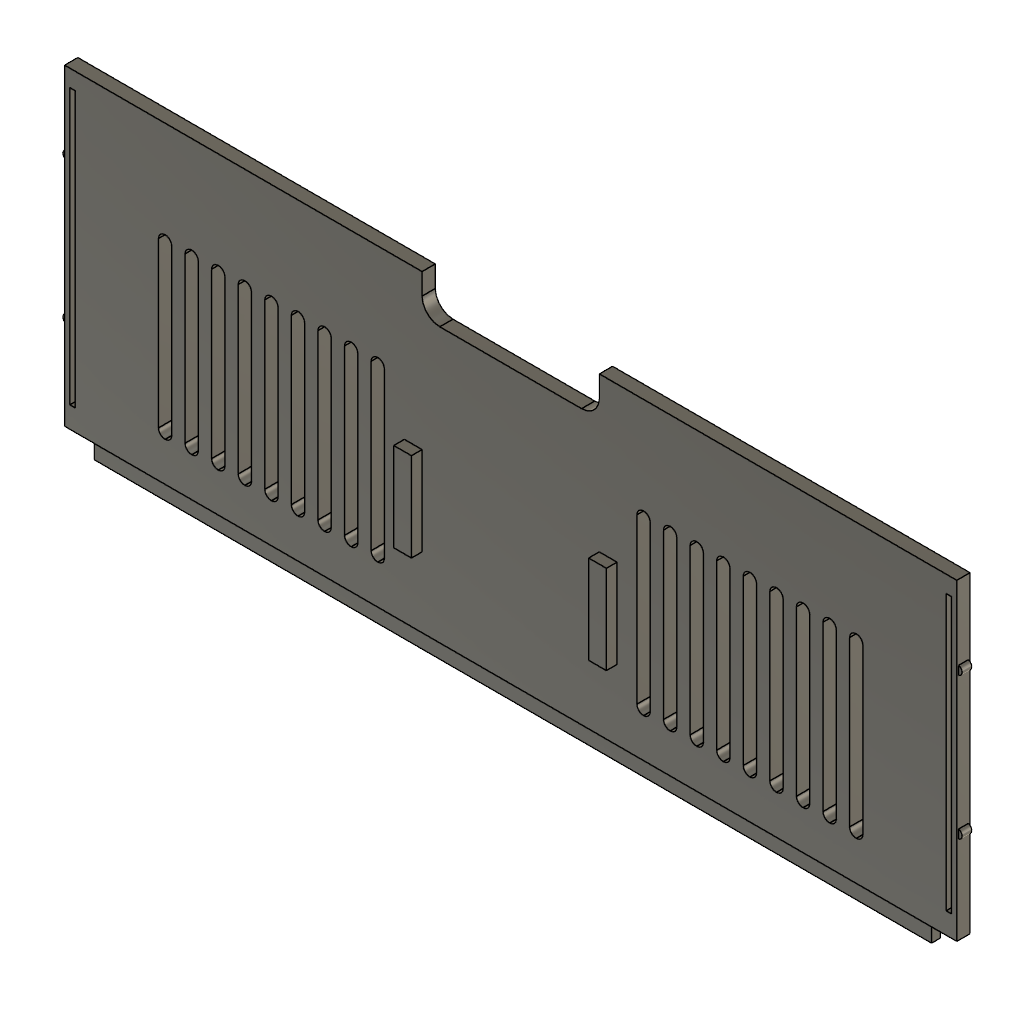
Back_Door (Autodesk Fusion 360 design; units mm, degrees)
part number: 2026-10-19-10-28-41-886
Autodesk Fusion 360 part; units mm, degrees
sketch "door_plate" plane through (0, 0, 0) normal (0, 0, 1) x (1, 0, 0)
  line L0 (-100.7, 229) -> (100.7, 229)
  line L1 (100.7, 229) -> (100.7, 232)
  line L2 (100.7, 232) -> (-100.7, 232)
  line L3 (-100.7, 232) -> (-100.7, 229)
extrude "door_plate (1)" add sketch "door_plate" along normal blind 70.6 from surface at 9.2
sketch "door_tongue" plane through (0, 0, 0) normal (0, 0, 1) x (1, 0, 0)
  line L0 (-94.5, 229.5) -> (94.5, 229.5)
  line L1 (94.5, 229.5) -> (94.5, 231.5)
  line L2 (94.5, 231.5) -> (-94.5, 231.5)
  line L3 (-94.5, 231.5) -> (-94.5, 229.5)
extrude "door_tongue (1)" add sketch "door_tongue" along normal blind 3.8 from surface at 5.5
sketch "door_flex_slot" plane through (0, 0, 0) normal (0, 0, 1) x (1, 0, 0)
  line L0 (98.3, 228.5) -> (99.5, 228.5)
  line L1 (99.5, 228.5) -> (99.5, 232.5)
  line L2 (99.5, 232.5) -> (98.3, 232.5)
  line L3 (98.3, 232.5) -> (98.3, 228.5)
extrude "door_flex_slot (1)" cut sketch "door_flex_slot" along normal blind 62 from surface at 14
sketch "door_bump" plane through (0, 0, 0) normal (0, 1, 0) x (1, 0, 0)
  circle A0 centre (100.5, -30) radius 1
  circle A1 centre (100.5, -62) radius 1
extrude "door_bump (1)" add sketch "door_bump" along normal blind 2.2 from surface at 229.4
sketch "door_bumper" plane through (0, 0, 0) normal (0, 0, 1) x (1, 0, 0)
  line L0 (20, 226.6) -> (24, 226.6)
  line L1 (24, 226.6) -> (24, 229.01)
  line L2 (24, 229.01) -> (20, 229.01)
  line L3 (20, 229.01) -> (20, 226.6)
extrude "door_bumper (1)" add sketch "door_bumper" along normal blind 20 from surface at 25
sketch "door_flex_slot (1)" plane through (0, 0, 0) normal (0, 0, 1) x (1, 0, 0)
  line L0 (-99.5, 228.5) -> (-98.3, 228.5)
  line L1 (-98.3, 228.5) -> (-98.3, 232.5)
  line L2 (-98.3, 232.5) -> (-99.5, 232.5)
  line L3 (-99.5, 232.5) -> (-99.5, 228.5)
extrude "door_flex_slot (2)" cut sketch "door_flex_slot (1)" along normal blind 62 from surface at 14
sketch "door_bump (1)" plane through (0, 0, 0) normal (0, 1, 0) x (1, 0, 0)
  circle A0 centre (-100.5, -30) radius 1
  circle A1 centre (-100.5, -62) radius 1
extrude "door_bump (2)" add sketch "door_bump (1)" along normal blind 2.2 from surface at 229.4
sketch "door_bumper (1)" plane through (0, 0, 0) normal (0, 0, 1) x (1, 0, 0)
  line L0 (-24, 226.6) -> (-20, 226.6)
  line L1 (-20, 226.6) -> (-20, 229.01)
  line L2 (-20, 229.01) -> (-24, 229.01)
  line L3 (-24, 229.01) -> (-24, 226.6)
extrude "door_bumper (2)" add sketch "door_bumper (1)" along normal blind 20 from surface at 25
sketch "door_finger_notch" plane through (0, 0, 0) normal (0, 1, 0) x (1, 0, 0)
  line L0 (-16, -71) -> (16, -71)
  arc A0 (20, -75) -> (16, -71) centre (16, -75) ccw
  line L1 (20, -75) -> (20, -81)
  arc A1 (16, -85) -> (20, -81) centre (16, -81) ccw
  line L2 (16, -85) -> (-16, -85)
  arc A2 (-20, -81) -> (-16, -85) centre (-16, -81) ccw
  line L3 (-20, -81) -> (-20, -75)
  arc A3 (-16, -71) -> (-20, -75) centre (-16, -75) ccw
extrude "door_finger_notch (1)" cut sketch "door_finger_notch" along normal blind 4 from surface at 228.5
sketch "door_vents" plane through (0, 0, 0) normal (0, 1, 0) x (1, 0, 0)
  line L0 (29.99, -18) -> (30.01, -18)
  arc A0 (31.5, -19.49) -> (30.01, -18) centre (30.01, -19.49) ccw
  line L1 (31.5, -19.49) -> (31.5, -56.51)
  arc A1 (30.01, -58) -> (31.5, -56.51) centre (30.01, -56.51) ccw
  line L2 (30.01, -58) -> (29.99, -58)
  arc A2 (28.5, -56.51) -> (29.99, -58) centre (29.99, -56.51) ccw
  line L3 (28.5, -56.51) -> (28.5, -19.49)
  arc A3 (29.99, -18) -> (28.5, -19.49) centre (29.99, -19.49) ccw
  line L4 (-30.01, -18) -> (-29.99, -18)
  arc A4 (-28.5, -19.49) -> (-29.99, -18) centre (-29.99, -19.49) ccw
  line L5 (-28.5, -19.49) -> (-28.5, -56.51)
  arc A5 (-29.99, -58) -> (-28.5, -56.51) centre (-29.99, -56.51) ccw
  line L6 (-29.99, -58) -> (-30.01, -58)
  arc A6 (-31.5, -56.51) -> (-30.01, -58) centre (-30.01, -56.51) ccw
  line L7 (-31.5, -56.51) -> (-31.5, -19.49)
  arc A7 (-30.01, -18) -> (-31.5, -19.49) centre (-30.01, -19.49) ccw
  line L8 (35.99, -18) -> (36.01, -18)
  arc A8 (37.5, -19.49) -> (36.01, -18) centre (36.01, -19.49) ccw
  line L9 (37.5, -19.49) -> (37.5, -56.51)
  arc A9 (36.01, -58) -> (37.5, -56.51) centre (36.01, -56.51) ccw
  line L10 (36.01, -58) -> (35.99, -58)
  arc A10 (34.5, -56.51) -> (35.99, -58) centre (35.99, -56.51) ccw
  line L11 (34.5, -56.51) -> (34.5, -19.49)
  arc A11 (35.99, -18) -> (34.5, -19.49) centre (35.99, -19.49) ccw
  line L12 (-36.01, -18) -> (-35.99, -18)
  arc A12 (-34.5, -19.49) -> (-35.99, -18) centre (-35.99, -19.49) ccw
  line L13 (-34.5, -19.49) -> (-34.5, -56.51)
  arc A13 (-35.99, -58) -> (-34.5, -56.51) centre (-35.99, -56.51) ccw
  line L14 (-35.99, -58) -> (-36.01, -58)
  arc A14 (-37.5, -56.51) -> (-36.01, -58) centre (-36.01, -56.51) ccw
  line L15 (-37.5, -56.51) -> (-37.5, -19.49)
  arc A15 (-36.01, -18) -> (-37.5, -19.49) centre (-36.01, -19.49) ccw
  line L16 (41.99, -18) -> (42.01, -18)
  arc A16 (43.5, -19.49) -> (42.01, -18) centre (42.01, -19.49) ccw
  line L17 (43.5, -19.49) -> (43.5, -56.51)
  arc A17 (42.01, -58) -> (43.5, -56.51) centre (42.01, -56.51) ccw
  line L18 (42.01, -58) -> (41.99, -58)
  arc A18 (40.5, -56.51) -> (41.99, -58) centre (41.99, -56.51) ccw
  line L19 (40.5, -56.51) -> (40.5, -19.49)
  arc A19 (41.99, -18) -> (40.5, -19.49) centre (41.99, -19.49) ccw
  line L20 (-42.01, -18) -> (-41.99, -18)
  arc A20 (-40.5, -19.49) -> (-41.99, -18) centre (-41.99, -19.49) ccw
  line L21 (-40.5, -19.49) -> (-40.5, -56.51)
  arc A21 (-41.99, -58) -> (-40.5, -56.51) centre (-41.99, -56.51) ccw
  line L22 (-41.99, -58) -> (-42.01, -58)
  arc A22 (-43.5, -56.51) -> (-42.01, -58) centre (-42.01, -56.51) ccw
  line L23 (-43.5, -56.51) -> (-43.5, -19.49)
  arc A23 (-42.01, -18) -> (-43.5, -19.49) centre (-42.01, -19.49) ccw
  line L24 (47.99, -18) -> (48.01, -18)
  arc A24 (49.5, -19.49) -> (48.01, -18) centre (48.01, -19.49) ccw
  line L25 (49.5, -19.49) -> (49.5, -56.51)
  arc A25 (48.01, -58) -> (49.5, -56.51) centre (48.01, -56.51) ccw
  line L26 (48.01, -58) -> (47.99, -58)
  arc A26 (46.5, -56.51) -> (47.99, -58) centre (47.99, -56.51) ccw
  line L27 (46.5, -56.51) -> (46.5, -19.49)
  arc A27 (47.99, -18) -> (46.5, -19.49) centre (47.99, -19.49) ccw
  line L28 (-48.01, -18) -> (-47.99, -18)
  arc A28 (-46.5, -19.49) -> (-47.99, -18) centre (-47.99, -19.49) ccw
  line L29 (-46.5, -19.49) -> (-46.5, -56.51)
  arc A29 (-47.99, -58) -> (-46.5, -56.51) centre (-47.99, -56.51) ccw
  line L30 (-47.99, -58) -> (-48.01, -58)
  arc A30 (-49.5, -56.51) -> (-48.01, -58) centre (-48.01, -56.51) ccw
  line L31 (-49.5, -56.51) -> (-49.5, -19.49)
  arc A31 (-48.01, -18) -> (-49.5, -19.49) centre (-48.01, -19.49) ccw
  line L32 (53.99, -18) -> (54.01, -18)
  arc A32 (55.5, -19.49) -> (54.01, -18) centre (54.01, -19.49) ccw
  line L33 (55.5, -19.49) -> (55.5, -56.51)
  arc A33 (54.01, -58) -> (55.5, -56.51) centre (54.01, -56.51) ccw
  line L34 (54.01, -58) -> (53.99, -58)
  arc A34 (52.5, -56.51) -> (53.99, -58) centre (53.99, -56.51) ccw
  line L35 (52.5, -56.51) -> (52.5, -19.49)
  arc A35 (53.99, -18) -> (52.5, -19.49) centre (53.99, -19.49) ccw
  line L36 (-54.01, -18) -> (-53.99, -18)
  arc A36 (-52.5, -19.49) -> (-53.99, -18) centre (-53.99, -19.49) ccw
  line L37 (-52.5, -19.49) -> (-52.5, -56.51)
  arc A37 (-53.99, -58) -> (-52.5, -56.51) centre (-53.99, -56.51) ccw
  line L38 (-53.99, -58) -> (-54.01, -58)
  arc A38 (-55.5, -56.51) -> (-54.01, -58) centre (-54.01, -56.51) ccw
  line L39 (-55.5, -56.51) -> (-55.5, -19.49)
  arc A39 (-54.01, -18) -> (-55.5, -19.49) centre (-54.01, -19.49) ccw
  line L40 (59.99, -18) -> (60.01, -18)
  arc A40 (61.5, -19.49) -> (60.01, -18) centre (60.01, -19.49) ccw
  line L41 (61.5, -19.49) -> (61.5, -56.51)
  arc A41 (60.01, -58) -> (61.5, -56.51) centre (60.01, -56.51) ccw
  line L42 (60.01, -58) -> (59.99, -58)
  arc A42 (58.5, -56.51) -> (59.99, -58) centre (59.99, -56.51) ccw
  line L43 (58.5, -56.51) -> (58.5, -19.49)
  arc A43 (59.99, -18) -> (58.5, -19.49) centre (59.99, -19.49) ccw
  line L44 (-60.01, -18) -> (-59.99, -18)
  arc A44 (-58.5, -19.49) -> (-59.99, -18) centre (-59.99, -19.49) ccw
  line L45 (-58.5, -19.49) -> (-58.5, -56.51)
  arc A45 (-59.99, -58) -> (-58.5, -56.51) centre (-59.99, -56.51) ccw
  line L46 (-59.99, -58) -> (-60.01, -58)
  arc A46 (-61.5, -56.51) -> (-60.01, -58) centre (-60.01, -56.51) ccw
  line L47 (-61.5, -56.51) -> (-61.5, -19.49)
  arc A47 (-60.01, -18) -> (-61.5, -19.49) centre (-60.01, -19.49) ccw
  line L48 (65.99, -18) -> (66.01, -18)
  arc A48 (67.5, -19.49) -> (66.01, -18) centre (66.01, -19.49) ccw
  line L49 (67.5, -19.49) -> (67.5, -56.51)
  arc A49 (66.01, -58) -> (67.5, -56.51) centre (66.01, -56.51) ccw
  line L50 (66.01, -58) -> (65.99, -58)
  arc A50 (64.5, -56.51) -> (65.99, -58) centre (65.99, -56.51) ccw
  line L51 (64.5, -56.51) -> (64.5, -19.49)
  arc A51 (65.99, -18) -> (64.5, -19.49) centre (65.99, -19.49) ccw
  line L52 (-66.01, -18) -> (-65.99, -18)
  arc A52 (-64.5, -19.49) -> (-65.99, -18) centre (-65.99, -19.49) ccw
  line L53 (-64.5, -19.49) -> (-64.5, -56.51)
  arc A53 (-65.99, -58) -> (-64.5, -56.51) centre (-65.99, -56.51) ccw
  line L54 (-65.99, -58) -> (-66.01, -58)
  arc A54 (-67.5, -56.51) -> (-66.01, -58) centre (-66.01, -56.51) ccw
  line L55 (-67.5, -56.51) -> (-67.5, -19.49)
  arc A55 (-66.01, -18) -> (-67.5, -19.49) centre (-66.01, -19.49) ccw
  line L56 (71.99, -18) -> (72.01, -18)
  arc A56 (73.5, -19.49) -> (72.01, -18) centre (72.01, -19.49) ccw
  line L57 (73.5, -19.49) -> (73.5, -56.51)
  arc A57 (72.01, -58) -> (73.5, -56.51) centre (72.01, -56.51) ccw
  line L58 (72.01, -58) -> (71.99, -58)
  arc A58 (70.5, -56.51) -> (71.99, -58) centre (71.99, -56.51) ccw
  line L59 (70.5, -56.51) -> (70.5, -19.49)
  arc A59 (71.99, -18) -> (70.5, -19.49) centre (71.99, -19.49) ccw
  line L60 (-72.01, -18) -> (-71.99, -18)
  arc A60 (-70.5, -19.49) -> (-71.99, -18) centre (-71.99, -19.49) ccw
  line L61 (-70.5, -19.49) -> (-70.5, -56.51)
  arc A61 (-71.99, -58) -> (-70.5, -56.51) centre (-71.99, -56.51) ccw
  line L62 (-71.99, -58) -> (-72.01, -58)
  arc A62 (-73.5, -56.51) -> (-72.01, -58) centre (-72.01, -56.51) ccw
  line L63 (-73.5, -56.51) -> (-73.5, -19.49)
  arc A63 (-72.01, -18) -> (-73.5, -19.49) centre (-72.01, -19.49) ccw
  line L64 (77.99, -18) -> (78.01, -18)
  arc A64 (79.5, -19.49) -> (78.01, -18) centre (78.01, -19.49) ccw
  line L65 (79.5, -19.49) -> (79.5, -56.51)
  arc A65 (78.01, -58) -> (79.5, -56.51) centre (78.01, -56.51) ccw
  line L66 (78.01, -58) -> (77.99, -58)
  arc A66 (76.5, -56.51) -> (77.99, -58) centre (77.99, -56.51) ccw
  line L67 (76.5, -56.51) -> (76.5, -19.49)
  arc A67 (77.99, -18) -> (76.5, -19.49) centre (77.99, -19.49) ccw
  line L68 (-78.01, -18) -> (-77.99, -18)
  arc A68 (-76.5, -19.49) -> (-77.99, -18) centre (-77.99, -19.49) ccw
  line L69 (-76.5, -19.49) -> (-76.5, -56.51)
  arc A69 (-77.99, -58) -> (-76.5, -56.51) centre (-77.99, -56.51) ccw
  line L70 (-77.99, -58) -> (-78.01, -58)
  arc A70 (-79.5, -56.51) -> (-78.01, -58) centre (-78.01, -56.51) ccw
  line L71 (-79.5, -56.51) -> (-79.5, -19.49)
  arc A71 (-78.01, -18) -> (-79.5, -19.49) centre (-78.01, -19.49) ccw
extrude "door_vents (1)" cut sketch "door_vents" along normal blind 4 from surface at 228.5
sketch "surge_mark" plane through (0, 0, 0) normal (0, 1, 0) x (1, 0, 0)
  circle A0 centre (0, -40) radius 18
  line L0 (5.2051, -38.7127) -> (-1.107, -54.8795)
  line L1 (-1.107, -54.8795) -> (-5.9778, -46.5759)
  line L2 (-5.9778, -46.5759) -> (0.1503, -42.2742)
  line L3 (0.1503, -42.2742) -> (-2.9177, -38.4458)
  line L4 (-2.9177, -38.4458) -> (-5.9853, -34.6172)
  line L5 (-5.9853, -34.6172) -> (3.775, -27.1341)
  line L6 (3.775, -27.1341) -> (0.8051, -37.1015)
  line L7 (0.8051, -37.1015) -> (5.2051, -38.7127)
extrude "surge_mark (1)" cut sketch "surge_mark" against normal blind 1.3 from surface at 232.5
equation "d1012 = -( 1.30 mm )"
named bodies: "Back Door"
